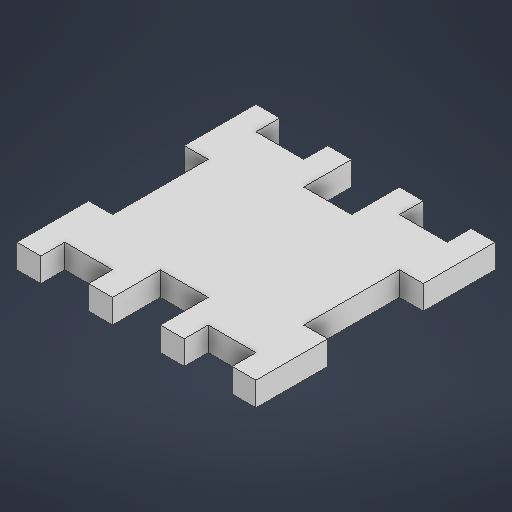
# Autodesk Inventor part: Tapa
Saved by Autodesk Inventor 2025.2 (Build 292293000, 293)
## iProperties
Created: 2025-06-04
Part Number: Tapa
Material: Genérico
Document SubType Name: Modeling
Designer: Niko
Density: 1 g/cm^3
Appearance: Valor por defecto
Author: Niko
Autodesk Inventor part; units mm, degrees
ref_plane "YZ Plane" through (0, 0, 0) normal (1, 0, 0) x (0, 1, 0)
ref_plane "XZ Plane" through (0, 0, 0) normal (0, 1, 0) x (-1, 0, 0)
ref_plane "XY Plane" through (0, 0, 0) normal (0, 0, 1) x (1, 0, 0)
sketch "Boceto1" plane through (0, 0, 0) normal (0, 1, 0) x (-1, 0, 0)
  line L0 (-5, 25) -> (-5, 15)
  line L1 (-5, 15) -> (5, 15)
  line L2 (5, 15) -> (5, 25)
  line L3 (-5, -25) -> (-5, -15)
  line L4 (-5, -15) -> (5, -15)
  line L5 (5, -15) -> (5, -25)
  line L6 (-25, 25) -> (-20, 25)
  line L7 (-10, 25) -> (-10, 20)
  line L8 (-10, 20) -> (-20, 20)
  line L9 (-20, 20) -> (-20, 25)
  line L10 (-10, -25) -> (-10, -20)
  line L11 (-10, -20) -> (-20, -20)
  line L12 (-20, -20) -> (-20, -25)
  line L13 (25, 25) -> (20, 25)
  line L14 (10, 25) -> (10, 20)
  line L15 (10, 20) -> (20, 20)
  line L16 (20, 20) -> (20, 25)
  line L17 (10, -25) -> (10, -20)
  line L18 (10, -20) -> (20, -20)
  line L19 (20, -20) -> (20, -25)
  line L20 (20, -25) -> (25, -25)
  line L21 (25, 25) -> (20, 25)
  line L22 (10, 25) -> (5, 25)
  line L23 (-5, 25) -> (-10, 25)
  line L24 (-20, 25) -> (-25, 25)
  line L25 (5, -25) -> (10, -25)
  line L26 (-25, -25) -> (-20, -25)
  line L27 (-10, -25) -> (-5, -25)
  line L28 (25, -20) -> (25, -10)
  line L29 (25, -10) -> (20, -10)
  line L30 (20, -10) -> (20, 10)
  line L31 (20, 10) -> (25, 10)
  line L32 (-25, -10) -> (-20, -10)
  line L33 (-20, -10) -> (-20, 10)
  line L34 (-20, 10) -> (-25, 10)
  line L35 (25, -25) -> (25, -10)
  line L36 (25, 10) -> (25, 25)
  line L37 (-25, 25) -> (-25, 10)
  line L38 (-25, -10) -> (-25, -25)
  point P0 (0, 0)
  constraints: 78 end point, 26 parallel, 12 perpendicular, 7 point on line, 4 horizontal
extrude "Extrusión2" add sketch "Boceto1" along normal blind 5
